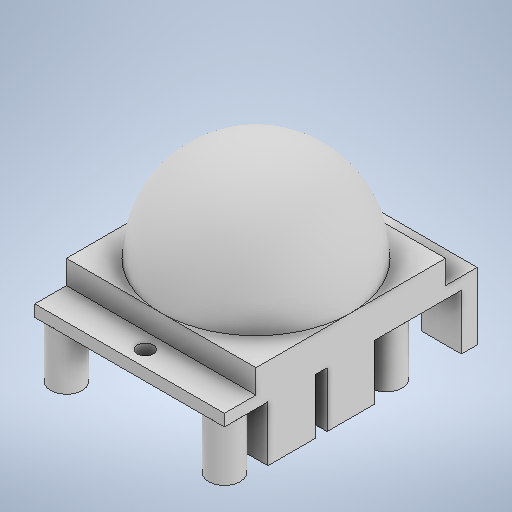
# Autodesk Inventor part: PIR센서
Saved by Autodesk Inventor 2025.3 (Build 293356030, 356C)
## iProperties
Created: 2025-09-11
Part Number: PIR센서
Material: 일반
Document SubType Name: Modeling
Designer: work
Density: 1 g/cm^3
Appearance: 기본값
Author: work
Autodesk Inventor part; units mm, degrees
ref_plane "YZ Plane" through (0, 0, 0) normal (1, 0, 0) x (0, 1, 0)
ref_plane "XZ Plane" through (0, 0, 0) normal (0, 1, 0) x (-1, 0, 0)
ref_plane "XY Plane" through (0, 0, 0) normal (0, 0, 1) x (1, 0, 0)
sketch "스케치1" plane through (0, 0, 0) normal (0, 1, 0) x (-1, 0, 0)
  line L0 (0, 0) -> (24, 0)
  line L1 (24, 0) -> (24, -32)
  line L2 (24, -32) -> (0, -32)
  line L3 (0, -32) -> (0, 0)
  dimension "d0" = 24
  dimension "d1" = 32
  constraints: 8 end point, 2 parallel, 1 horizontal, 1 perpendicular
  measures "d0" distance of L1.end L2.end
  measures "d1" distance of L0.end L1.end
extrude "돌출1" add sketch "스케치1" along normal blind 1.5
sketch "스케치2" plane through (0, 1.5, 0) normal (0, 1, 0) x (1, 0, 0)
  line L0 (-24, 32) -> (-24, 0) projected
  line L1 (0, 0) -> (0, 32) projected
  line L2 (-24, 4) -> (0, 4)
  line L3 (0, 4) -> (0, 28)
  line L4 (0, 28) -> (-24, 28)
  line L5 (-24, 28) -> (-24, 4)
  line L6 (0, 32) -> (-24, 32) projected
  line L7 (-24, 32) -> (-24, 0) projected
  line L8 (-24, 0) -> (0, 0) projected
  line L9 (0, 0) -> (0, 32) projected
  point P0 (0, 16)
  point P1 (-24, 28)
  point P2 (0, 4)
  dimension "d4" = 24
  constraints: 8 end point, 2 midpoint, 2 parallel, 2 point on line, 1 horizontal, 1 perpendicular
  measures "d4" distance between parallel lines of L4 L2
extrude "돌출2" add sketch "스케치2" along normal blind 3 contours L4 L1 L2 L0
sketch "스케치3" plane through (0, 4.5, 0) normal (0, 1, 0) x (1, 0, 0)
  line L0 (-24, 28) -> (-24, 4) projected
  line L1 (-24, 16) -> (0, 16) construction
  line L2 (0, 28) -> (-24, 28) projected
  line L3 (-12, 28) -> (-12, 4)
  line L4 (-24, 4) -> (0, 4) projected
  circle A0 centre (-12, 16) radius 12
  point P0 (0, 0)
  constraints: 4 end point, 4 midpoint, 1 horizontal, 3 other
revolve "회전1" add sketch "스케치3" angle 180 about axis through (-12, 4.5, -28) along (0, 0, 1) picked at (-10.2645, 19.6039) contours A0 L3
sketch "스케치4" plane through (0, 1.5, 0) normal (0, 1, 0) x (1, 0, 0)
  line L0 (-24, 0) -> (0, 0) projected
  line L1 (-12, 0) -> (-12, 32) construction
  line L2 (0, 32) -> (-24, 32) projected
  point P0 (-12, 2)
  point P1 (-12, 30)
  dimension "d8" = 2
  dimension "d9" = 2
  constraints: 2 end point, 2 midpoint, 2 point on line
  measures "d8" distance from line of L2 point (-12, 30)
  measures "d9" distance from line of L0 point (-12, 2)
hole "구멍1" at (-12, 1.5, -2) at (-12, 1.5, -30) direction (0, -1, 0) diameter 2 end through all
sketch "스케치5" plane through (0, 0, 0) normal (0, -1, 0) x (1, 0, 0)
  line L0 (-24, 0) -> (0, 0) projected
  line L1 (-4, 0) -> (-4, -32) construction
  line L2 (0, -32) -> (-24, -32) projected
  line L3 (0, 0) -> (0, -32) projected
  circle A0 centre (-2, -2) radius 2
  circle A1 centre (-2, -22.5) radius 2
  line L4 (0, -5.5) -> (-4, -5.5)
  line L5 (-4, -5.5) -> (-4, -11.5)
  line L6 (-4, -11.5) -> (0, -11.5)
  line L7 (0, -11.5) -> (0, -5.5)
  line L8 (0, -13) -> (-4, -13)
  line L9 (-4, -13) -> (-4, -19)
  line L10 (-4, -19) -> (0, -19)
  line L11 (0, -19) -> (0, -13)
  line L12 (0, -32) -> (-5, -32)
  line L13 (-5, -32) -> (-5, -30)
  line L14 (-5, -30) -> (0, -30)
  line L15 (0, -30) -> (0, -32)
  circle A2 centre (-22, -2) radius 2
  circle A3 centre (-22, -30) radius 2
  line L16 (-24, -32) -> (-24, 0) projected
  point P0 (0, -19)
  point P1 (0, -11.5)
  dimension "d17" = 4
  dimension "d18" = 6
  dimension "d19" = 6
  dimension "d20" = 1.5
  dimension "d21" = 1.5
  dimension "d22" = 1.5
  dimension "d23" = 5
  dimension "d24" = 2
  dimension "d25" = 4
  dimension "d26" = 4
  constraints: 26 end point, 9 tangent, 6 parallel, 6 point on line, 4 centre point, 3 horizontal, 3 perpendicular, 1 vertical
  measures "d17" distance between parallel lines of L3 L1
  measures "d18" distance of L5.end L4.end
  measures "d19" distance of L9.end L8.end
  measures "d20" distance between parallel lines of L8 L6
  measures "d21" distance edge to line of A0 L4
  measures "d22" distance edge to line of A1 L10
  measures "d23" distance of L13.end L14.end
  measures "d24" distance of L12.end L13.end
  measures "d25" diameter of A2
  measures "d26" diameter of A3
extrude "돌출3" add sketch "스케치5" along normal blind 7 contours A1 | A2 | A0 | A3 | L3 L6 L5 L4 | L13 L14 L3 L2 | L3 L10 L9 L8
sketch "스케치6" plane through (0, 0, 0) normal (0, -1, 0) x (1, 0, 0)
  line L0 (-21.5, -12.5) -> (-24, -12.5)
  line L1 (-24, -12.5) -> (-24, -19.5)
  line L2 (-24, -19.5) -> (-21.5, -19.5)
  line L3 (-21.5, -19.5) -> (-21.5, -12.5)
  line L4 (-24, -30) -> (-24, -2) projected
  point P0 (0, 0)
  point P1 (-24, -16)
  dimension "d29" = 2.5
  dimension "d30" = 7
  constraints: 8 end point, 2 midpoint, 2 parallel, 1 horizontal, 1 perpendicular
  measures "d29" distance of L2.end L1.end
  measures "d30" distance of L1.end L0.end
extrude "돌출4" add sketch "스케치6" along normal blind 2.5
